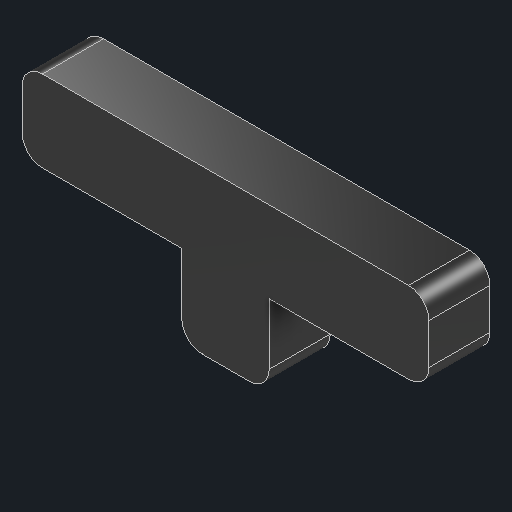
# Autodesk Inventor part: Laser Rx Slot
Saved by Autodesk Inventor 2027.1 (Build 311270010, 270A)
## iProperties
Created: 2026-10-18
Part Number: Laser Rx Slot
Material: MDF Medium Density Fiberboard
Document SubType Name: Modeling
Designer: Ahmed
Density: 0.8 g/cm^3
Appearance: Glossy - Black
Mass: 0.23019 g
Surface Area: 3.52099 cm^2
Volume: 0.287737 cm^3
Author: Ahmed
Autodesk Inventor part; units mm, degrees
ref_plane "YZ Plane" through (0, 0, 0) normal (1, 0, 0) x (0, 1, 0)
ref_plane "XZ Plane" through (0, 0, 0) normal (0, 1, 0) x (-1, 0, 0)
ref_plane "XY Plane" through (0, 0, 0) normal (0, 0, 1) x (1, 0, 0)
sketch "Sketch1" plane through (0, 0, 0) normal (0, 0, 1) x (1, 0, 0)
  line L0 (10, 2) -> (10, -2)
  line L1 (10, -2) -> (-10, -2)
  line L2 (-10, -2) -> (-10, 2)
  line L3 (-2.15, -2) -> (2.15, -2)
  line L4 (2.15, -2) -> (2.15, -6)
  line L5 (2.15, -6) -> (-2.15, -6)
  line L6 (-2.15, -6) -> (-2.15, -2)
  line L7 (-10, 2) -> (10, 2)
  point P0 (0, -2)
  point P1 (2.15, -2)
  point P2 (-2.15, -2)
  point P3 (0, -6)
  point P4 (0, 0)
  point P5 (-10, 0)
  dimension "d6" = 4
  dimension "d10" = 4.3
  dimension "d11" = 4
  dimension "d13" = 4
  dimension "d14" = 20
  constraints: 16 end point, 4 midpoint, 3 parallel, 2 horizontal, 1 horizontal alignment, 1 perpendicular, 1 vertical, 1 vertical alignment
  measures "d6" distance of L0.start L0.end
  measures "d10" distance of L4.end L5.end
  measures "d11" distance of L3.end L4.end
  measures "d13" distance of L1.end L2.end
  measures "d14" distance of L2.end L0.start
extrude "Extrusion1" add sketch "Sketch1" along normal blind 3
fillet "Fillet1" radius 1 6 edges at (10, 2, 1.5) (10, -2, 1.5) (-10, 2, 1.5) (-10, -2, 1.5) (-2.15, -6, 1.5) (2.15, -6, 1.5)
equation "\"GridProcutClearance\" = 5"
equation "\"GridBorderThickness\" = 5"
equation "\"GridBorderFillets\" = 7"
equation "\"GridTotalSize\" = 65"
equation "\"GridRobotClearance\" = 65"
equation "\"AluminiumExtrusionClearance\" = 35"
equation "\"BaseTotalLength\" = 885"
equation "\"WorkspaceLength\" = 515"
equation "\"WorkspaceHeight\" = 183"
equation "\"AxesBaseFillet\" = 15"
equation "\"Zaxis\" = 197"
equation "\"ProductTotalHeight\" = 45"
equation "\"VerticalStroke\" = 105"
equation "\"BackArea\" = 165"
equation "\"CylinderStroke\" = 75"
equation "\"BoxesWidth\" = 125"
equation "\"BaseWoodThickness\" = 7"
equation "\"Kerf\" = 0.3"
equation "\"RxThickness\" = 1.8"
equation "\"support_2\" = 265"
body "Solid1"
